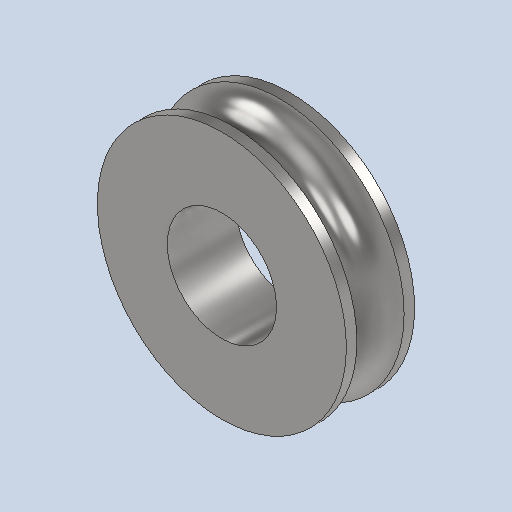
# Autodesk Inventor part: Hantelrolle
Saved by Autodesk Inventor 2027.1 (Build 311270010, 270A)
## iProperties
Created: 2026-07-29
Part Number: Hantelrolle
Material: Stahl, Legierung
Document SubType Name: Modeling
Designer: moest
Density: 7.73 g/cm^3
Appearance: Halbpoliert
Author: moest
Autodesk Inventor part; units mm, degrees
ref_plane "YZ Plane" through (0, 0, 0) normal (1, 0, 0) x (0, 1, 0)
ref_plane "XZ Plane" through (0, 0, 0) normal (0, 1, 0) x (-1, 0, 0)
ref_plane "XY Plane" through (0, 0, 0) normal (0, 0, 1) x (1, 0, 0)
sketch "Skizze1" plane through (0, 0, 0) normal (0, 0, 1) x (1, 0, 0)
  line L0 (0, 0) -> (36.5, 0)
  line L1 (36.5, 0) -> (36.5, 20)
  line L2 (36.5, 20) -> (0, 20)
  line L3 (0, 20) -> (0, 0)
  line L4 (0, 10) -> (31, 10)
  line L5 (31, 10) -> (31, 20)
  line L6 (31, 10) -> (31, 0)
  line L7 (0, 17) -> (36.5, 17)
  line L8 (0, 3) -> (36.5, 3)
  line L9 (31, 10) -> (37.5, 10)
  circle A0 centre (37.5, 10) radius 7
  point P0 (36.5, 3.0718)
  point P1 (36.5, 16.9282)
  dimension "d0" = 36.5
  dimension "d1" = 20
  dimension "d2" = 31
  dimension "d3" = 6.5
  constraints: 20 end point, 8 point on line, 4 perpendicular, 2 horizontal, 2 parallel, 1 centre point, 1 coincident, 1 midpoint, 1 tangent
  measures "d0" distance of L2.end L1.end
  measures "d1" distance of L1.end L0.end
  measures "d2" distance of L4.start L4.end
  measures "d3" distance of L4.end L9.end
revolve "Umdrehung1" add sketch "Skizze1" angle 360 about axis through (0, 20, 0) along (0, -1, 0) contours L3 L8 L6 L0 | L6 L8 L1 L0 | L3 L4 A0 L6 L8 | L6 A0 L1 L8 | L3 L7 L5 A0 L4 | L3 L2 L5 L7 | L7 L1 A0 L5 | L5 L2 L1 L7
sketch "Skizze2" plane through (0, 20, 0) normal (0, 1, 0) x (1, 0, 0)
  circle A0 centre (0, 0) radius 16
  dimension "d5" = 32
  constraints: 1 centre point, 1 coincident
  measures "d5" diameter of A0
extrude "Extrusion1" cut sketch "Skizze2" against normal blind 25.75
